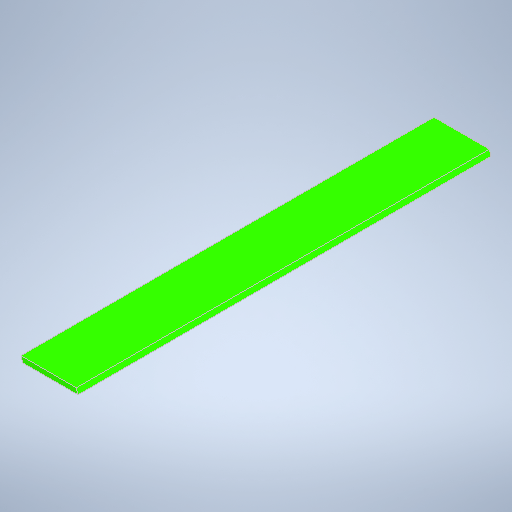
# Autodesk Inventor part: Low_Section_Plate
Saved by Autodesk Inventor 2026.2 (Build 302298000, 298)
## iProperties
Created: 2026-07-14
Part Number: Low_Section_Plate
Material: M-Foam PVC foam
Document SubType Name: Modeling
Designer: Taiye Raji
Density: 0.13 g/cm^3
Appearance: Generic
Mass: 727.793 g
Surface Area: 7217.7 cm^2
Volume: 5598.41 cm^3
Author: Taiye Raji
Autodesk Inventor part; units mm, degrees
ref_plane "YZ Plane" through (0, 0, 0) normal (1, 0, 0) x (0, 1, 0)
ref_plane "XZ Plane" through (0, 0, 0) normal (0, 1, 0) x (-1, 0, 0)
ref_plane "XY Plane" through (0, 0, 0) normal (0, 0, 1) x (1, 0, 0)
sketch "Sketch4" plane through (0, 0, 0) normal (0, 0, 1) x (1, 0, 0)
  line L0 (105.1462, -10) -> (-105.1462, -10)
  line L1 (-105.1462, -10) -> (-105.1462, 10)
  line L2 (-111.6446, 10) -> (105.1462, 10)
  line L3 (105.1462, 10) -> (105.1462, -10)
  line L4 (105.1462, -10) -> (-105.1462, 10) construction
  line L5 (-105.1462, -10) -> (105.1462, 10) construction
  line L6 (-105.1462, -10) -> (-111.6446, 10)
  line L7 (105.1462, -10) -> (98.6478, 10)
  point P0 (0, 0)
  dimension "d25" = 20
  dimension "d26" = 108
  dimension "d27" = 72
  dimension "d31" = 210.2924
  constraints: 16 end point, 2 midpoint, 2 parallel, 2 point on line, 1 horizontal, 1 perpendicular
  measures "d25" distance of L2.end L0.start
  measures "d26" angle of L0 L6
  measures "d27" angle of L0 L7
  measures "d31" distance of L2.end L1.end
extrude "Extrusion3" add sketch "Sketch4" against normal blind 1566 contours L0 L1 L2 L7 | L6 L2 L1
body "Solid2"
